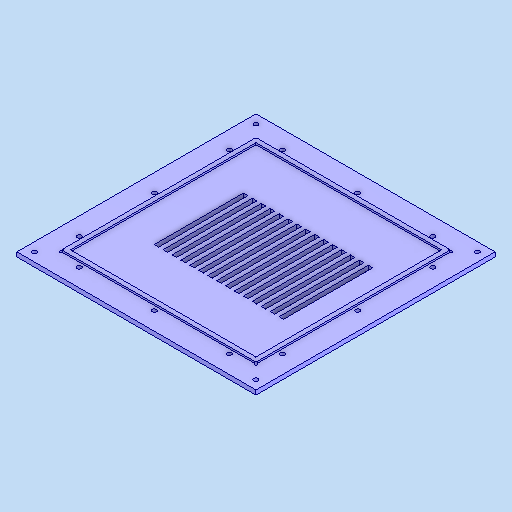
# Autodesk Inventor part: Base_Externa
Saved by Autodesk Inventor 2027 (Build 310192000, 192)
## iProperties
Created: 2026-11-03
Part Number: Base_Externa
Material: Plástico PAEK
Document SubType Name: Modeling
Designer: alex
Density: 1.32 g/cm^3
Appearance: Suave - Blanco
Author: alex
Autodesk Inventor part; units mm, degrees
ref_plane "YZ Plane" through (0, 0, 0) normal (1, 0, 0) x (0, 1, 0)
ref_plane "XZ Plane" through (0, 0, 0) normal (0, 1, 0) x (-1, 0, 0)
ref_plane "XY Plane" through (0, 0, 0) normal (0, 0, 1) x (1, 0, 0)
sketch "Boceto1" plane through (0, 0, 0) normal (0, 1, 0) x (-1, 0, 0)
  arc A0 (-28.3314, 127.2798) -> (-23.3314, 132.2798) centre (-28.3314, 132.2798) ccw
  circle A1 centre (-28.3314, 132.2798) radius 2.5
  line L0 (-33.3314, 127.2798) -> (-28.3314, 127.2798)
  arc A2 (-28.3314, 127.2798) -> (-23.3314, 132.2798) centre (-28.3314, 132.2798) ccw
  line L1 (-23.3314, 137.2798) -> (-23.3314, 132.2798)
  line L2 (-23.3314, 132.2798) -> (-23.3314, 137.2798)
  line L3 (-23.3314, 137.2798) -> (214.6686, 137.2798)
  line L4 (214.6686, 137.2798) -> (214.6686, 132.2798)
  arc A3 (214.6686, 132.2798) -> (219.6686, 127.2798) centre (219.6686, 132.2798) ccw
  line L5 (224.6686, 127.2798) -> (224.6686, -25.7202)
  line L6 (219.6686, 127.2798) -> (224.6686, 127.2798)
  line L7 (224.6686, -115.7202) -> (224.6686, -110.7202)
  line L8 (224.6686, 127.2798) -> (224.6686, -110.7202)
  line L9 (224.6686, -110.7202) -> (219.6686, -110.7202)
  arc A4 (219.6686, -110.7202) -> (214.6686, -115.7202) centre (219.6686, -115.7202) ccw
  line L10 (-23.3314, -120.7202) -> (214.6686, -120.7202)
  line L11 (214.6686, -115.7202) -> (214.6686, -120.7202)
  line L12 (-23.3314, -120.7202) -> (-23.3314, -115.7202)
  line L13 (214.6686, -120.7202) -> (-23.3314, -120.7202)
  line L14 (-23.3314, -120.7202) -> (-23.3314, -115.7202)
  line L15 (-33.3314, -110.7202) -> (-33.3314, 127.2798)
  arc A5 (219.6686, -110.7202) -> (214.6686, -115.7202) centre (219.6686, -115.7202) ccw
  arc A6 (-23.3314, -115.7202) -> (-28.3314, -110.7202) centre (-28.3314, -115.7202) ccw
  arc A7 (-23.3314, -115.7202) -> (-28.3314, -110.7202) centre (-28.3314, -115.7202) ccw
  line L16 (-28.3314, -110.7202) -> (-33.3314, -110.7202)
  line L17 (-28.3314, -110.7202) -> (-33.3314, -110.7202)
  line L18 (95.6686, 137.2798) -> (95.6686, -120.7202)
  line L19 (224.6686, 8.2798) -> (-33.3314, 8.2798)
  circle A8 centre (209.6686, 92.2798) radius 2.5
  circle A9 centre (209.6686, 8.2798) radius 2.5
  circle A10 centre (209.6686, -75.7202) radius 2.5
  circle A11 centre (179.6686, -105.7202) radius 2.5
  circle A12 centre (95.6686, -105.7202) radius 2.5
  circle A13 centre (11.6686, -105.7202) radius 2.5
  circle A14 centre (-18.3314, -75.7202) radius 2.5
  circle A15 centre (-18.3314, 8.2798) radius 2.5
  circle A16 centre (-18.3314, 92.2798) radius 2.5
  circle A17 centre (11.6686, 122.2798) radius 2.5
  circle A18 centre (95.6686, 122.2798) radius 2.5
  circle A19 centre (179.6686, 122.2798) radius 2.5
  line L20 (229.6686, 142.2798) -> (-38.3314, 142.2798)
  line L21 (-38.3314, 142.2798) -> (-38.3314, -125.7202)
  line L22 (-38.3314, -125.7202) -> (229.6686, -125.7202)
  line L23 (229.6686, -125.7202) -> (229.6686, 142.2798)
  circle A20 centre (219.6686, 132.2798) radius 2.5
  circle A21 centre (219.6686, -115.7202) radius 2.5
  circle A22 centre (-28.3314, -115.7202) radius 2.5
  line L24 (204.6686, 117.2798) -> (-13.3314, 117.2798)
  line L25 (-13.3314, 117.2798) -> (-13.3314, -100.7202)
  line L26 (-13.3314, -100.7202) -> (204.6686, -100.7202)
  line L27 (204.6686, -100.7202) -> (204.6686, 117.2798)
  line L28 (-8.3314, 112.2798) -> (199.6686, 112.2798)
  line L29 (199.6686, 112.2798) -> (199.6686, -95.7202)
  line L30 (199.6686, -95.7202) -> (-8.3314, -95.7202)
  line L31 (-8.3314, -95.7202) -> (-8.3314, 112.2798)
  point P0 (0, 0)
  point P1 (-230.3314, 137.2798)
  dimension "d0" = 258
  dimension "d1" = 258
  dimension "d2" = 238
  dimension "d3" = 238
  dimension "d4" = 15
  dimension "d5" = 15
  dimension "d6" = 15
  dimension "d7" = 84
  dimension "d8" = 84
  dimension "d9" = 84
  dimension "d10" = 84
  dimension "d11" = 15
  dimension "d12" = 15
  dimension "d13" = 15
  dimension "d14" = 84
  dimension "d15" = 84
  dimension "d16" = 84
  dimension "d17" = 84
  dimension "d18" = 15
  dimension "d19" = 15
  dimension "d20" = 15
  dimension "d21" = 15
  dimension "d22" = 15
  dimension "d23" = 15
  dimension "d24" = 5
  dimension "d25" = 5
  dimension "d26" = 5
  dimension "d27" = 5
  dimension "d28" = 5
  dimension "d29" = 5
  dimension "d30" = 5
  dimension "d31" = 5
  dimension "d32" = 5
  dimension "d33" = 5
  dimension "d34" = 5
  dimension "d35" = 5
  dimension "d36" = 5
  dimension "d37" = 5
  dimension "d38" = 5
  dimension "d39" = 5
  dimension "d40" = 5
  dimension "d41" = 5
  dimension "d42" = 5
  dimension "d43" = 20
  dimension "d44" = 20
  dimension "d45" = 20
  dimension "d46" = 20
  dimension "d49" = 5
  dimension "d50" = 5
  dimension "d51" = 5
  dimension "d52" = 5
  constraints: 64 end point, 23 centre point, 16 coincident, 14 point on circle, 10 perpendicular, 7 parallel, 4 horizontal, 4 midpoint, 4 point on line, 2 concentric, 1 collinear, 1 vertical
  measures "d0" distance between parallel lines of L15 L8
  measures "d1" distance between parallel lines of L10 L3
  measures "d2" distance of L1.start L3.end
  measures "d3" distance of L15.start L0.start
  measures "d4" distance from line of L3 point (95.669, 122.28)
  measures "d5" distance from line of L3 point (179.669, 122.28)
  measures "d6" distance from line of point (11.669, 122.28) L3
  measures "d7" distance from line of point (179.669, 122.28) L18
  measures "d8" distance from line of L18 point (11.669, 122.28)
  measures "d9" distance from line of point (11.669, -105.72) L18
  measures "d10" distance from line of point (179.669, -105.72) L18
  measures "d11" distance from line of L10 point (95.669, -105.72)
  measures "d12" distance from line of point (179.669, -105.72) L10
  measures "d13" distance from line of point (11.669, -105.72) L10
  measures "d14" distance from line of point (209.669, 92.28) L19
  measures "d15" distance from line of point (209.669, -75.72) L19
  measures "d16" distance from line of point (-18.331, 92.28) L19
  measures "d17" distance from line of point (-18.331, -75.72) L19
  measures "d18" distance from line of L15 point (-18.331, 92.28)
  measures "d19" distance from line of L15 point (-18.331, -75.72)
  measures "d20" distance from line of L15 point (-18.331, 8.28)
  measures "d21" distance from line of point (209.669, 92.28) L8
  measures "d22" distance from line of point (209.669, 8.28) L8
  measures "d23" distance from line of point (209.669, -75.72) L8
  measures "d24" diameter of A8
  measures "d25" diameter of A9
  measures "d26" diameter of A10
  measures "d27" diameter of A11
  measures "d28" diameter of A12
  measures "d29" diameter of A13
  measures "d30" diameter of A14
  measures "d31" diameter of A15
  measures "d32" diameter of A16
  measures "d33" diameter of A17
  measures "d34" diameter of A18
  measures "d35" diameter of A19
  measures "d36" distance between parallel lines of L20 L3
  measures "d37" distance between parallel lines of L21 L15
  measures "d38" distance between parallel lines of L22 L13
  measures "d39" distance between parallel lines of L23 L8
  measures "d40" diameter of A20
  measures "d41" diameter of A21
  measures "d42" diameter of A22
  measures "d43" distance between parallel lines of L27 L5
  measures "d44" distance between parallel lines of L24 L3
  measures "d45" distance between parallel lines of L25 L15
  measures "d46" distance between parallel lines of L26 L13
  measures "d49" distance between parallel lines of L30 L26
  measures "d50" distance between parallel lines of L31 L25
  measures "d51" distance between parallel lines of L28 L24
  measures "d52" distance between parallel lines of L29 L27
extrude "Extrusión1" add sketch "Boceto1" along normal blind 5 contours A0 L1 L3 L18 A18 L24 L25 L19 A15 L15 L0 | L19 A15 L25 L26 L18 A12 L10 L12 A6 L16 L15 | L3 L4 A3 L6 L5 L19 A9 L27 L24 L18 A18 | L25 L24 L18 L28 L31 L19 | L19 L31 L30 L18 L26 L25 | L24 L27 L19 L29 L28 L18 | L31 L28 L18 L19 | L19 L18 L30 L31 | L28 L29 L19 L18 | L18 A12 L26 L27 L19 A9 L5 L8 L9 A4 L11 L10 | L19 L29 L30 L18 | L18 L30 L29 L19 L27 L26 | L23 L22 L21 L20
extrude "Extrusión2" add sketch "Boceto1" along normal blind 7 contours L25 L24 L18 L28 L31 L19 | L19 L31 L30 L18 L26 L25 | L24 L27 L19 L29 L28 L18 | L18 L30 L29 L19 L27 L26
sketch "Boceto2" plane through (0, 0, 0) normal (0, -1, 0) x (1, 0, 0)
  line L0 (-229.6686, 142.2798) -> (38.3314, 142.2798) projected
  line L1 (-229.6686, -125.7202) -> (-229.6686, 142.2798) projected
  line L2 (38.3314, 142.2798) -> (-229.6686, 142.2798)
  line L3 (-229.6686, 142.2798) -> (-229.6686, -125.7202)
  line L4 (-229.6686, -125.7202) -> (38.3314, -125.7202)
  line L5 (38.3314, -125.7202) -> (38.3314, 142.2798)
  line L6 (13.3314, 117.2798) -> (-204.6686, 117.2798) projected
  circle A0 centre (13.3314, 117.2798) radius 10
  line L7 (13.3314, 117.2798) -> (13.3314, -100.7202) projected
  circle A1 centre (13.3314, -100.7202) radius 10
  line L8 (-204.6686, 117.2798) -> (-204.6686, -100.7202) projected
  circle A2 centre (-204.6686, 117.2798) radius 10
  circle A3 centre (-204.6686, -100.7202) radius 10
  circle A4 centre (-204.6686, 117.2798) radius 7.5
  circle A5 centre (13.3314, 117.2798) radius 7.5
  circle A6 centre (13.3314, -100.7202) radius 7.5
  line L9 (-204.6686, -100.7202) -> (13.3314, -100.7202) projected
  circle A7 centre (-204.6686, -100.7202) radius 7.5
  point P0 (0, 0)
  dimension "d55" = 20
  dimension "d56" = 20
  dimension "d57" = 20
  dimension "d58" = 20
  dimension "d59" = 15
  dimension "d60" = 15
  dimension "d61" = 15
  dimension "d62" = 15
  constraints: 8 centre point, 8 end point, 6 coincident, 2 parallel, 1 horizontal, 1 perpendicular
  measures "d55" diameter of A0
  measures "d56" diameter of A1
  measures "d57" diameter of A2
  measures "d58" diameter of A3
  measures "d59" diameter of A4
  measures "d60" diameter of A5
  measures "d61" diameter of A6
  measures "d62" diameter of A7
extrude "Extrusión3" add sketch "Boceto2" along normal blind 5 contours A2 L8 A4 L6 | L6 A4 L8 A2 | A0 L7 A5 L6 | L6 A5 L7 A0 | A3 L9 A7 L8 | L8 A7 L9 A3 | A1 L9 A6 L7 | L7 A6 L9 A1
hole "Agujero1" at (13.3314, 0, 117.2798) at (13.3314, 0, -100.7202) at (-204.6686, 0, -100.7202) at (-204.6686, 0, 117.2798) direction (0, 1, 0) diameter 3 end through all
sketch "Boceto3" plane through (0, 0, 0) normal (0, -1, 0) x (1, 0, 0)
  line L0 (-14.7635, 58.2798) -> (-19.7635, 58.2798)
  line L1 (-19.7635, 58.2798) -> (-19.7635, -41.7202)
  line L2 (-19.7635, -41.7202) -> (-14.7635, -41.7202)
  line L3 (-14.7635, -41.7202) -> (-14.7635, 58.2798)
  line L4 (-229.6686, 142.2798) -> (38.3314, 142.2798) projected
  line L5 (38.3314, -125.7202) -> (-229.6686, -125.7202) projected
  line L6 (-24.7635, 58.2798) -> (-29.7635, 58.2798)
  line L7 (-29.7635, 58.2798) -> (-29.7635, -41.7202)
  line L8 (-29.7635, -41.7202) -> (-24.7635, -41.7202)
  line L9 (-24.7635, -41.7202) -> (-24.7635, 58.2798)
  line L10 (-34.7635, 58.2798) -> (-39.7635, 58.2798)
  line L11 (-39.7635, 58.2798) -> (-39.7635, -41.7202)
  line L12 (-39.7635, -41.7202) -> (-34.7635, -41.7202)
  line L13 (-34.7635, -41.7202) -> (-34.7635, 58.2798)
  line L14 (-44.7635, 58.2798) -> (-49.7635, 58.2798)
  line L15 (-49.7635, 58.2798) -> (-49.7635, -41.7202)
  line L16 (-49.7635, -41.7202) -> (-44.7635, -41.7202)
  line L17 (-44.7635, -41.7202) -> (-44.7635, 58.2798)
  line L18 (-54.7635, 58.2798) -> (-59.7635, 58.2798)
  line L19 (-59.7635, 58.2798) -> (-59.7635, -41.7202)
  line L20 (-59.7635, -41.7202) -> (-54.7635, -41.7202)
  line L21 (-54.7635, -41.7202) -> (-54.7635, 58.2798)
  line L22 (-64.7635, 58.2798) -> (-69.7635, 58.2798)
  line L23 (-69.7635, 58.2798) -> (-69.7635, -41.7202)
  line L24 (-69.7635, -41.7202) -> (-64.7635, -41.7202)
  line L25 (-64.7635, -41.7202) -> (-64.7635, 58.2798)
  line L26 (-74.7635, 58.2798) -> (-79.7635, 58.2798)
  line L27 (-79.7635, 58.2798) -> (-79.7635, -41.7202)
  line L28 (-79.7635, -41.7202) -> (-74.7635, -41.7202)
  line L29 (-74.7635, -41.7202) -> (-74.7635, 58.2798)
  line L30 (-84.7635, 58.2798) -> (-89.7635, 58.2798)
  line L31 (-89.7635, 58.2798) -> (-89.7635, -41.7202)
  line L32 (-89.7635, -41.7202) -> (-84.7635, -41.7202)
  line L33 (-84.7635, -41.7202) -> (-84.7635, 58.2798)
  line L34 (-94.7635, 58.2798) -> (-99.7635, 58.2798)
  line L35 (-99.7635, 58.2798) -> (-99.7635, -41.7202)
  line L36 (-99.7635, -41.7202) -> (-94.7635, -41.7202)
  line L37 (-94.7635, -41.7202) -> (-94.7635, 58.2798)
  line L38 (-104.7635, 58.2798) -> (-109.7635, 58.2798)
  line L39 (-109.7635, 58.2798) -> (-109.7635, -41.7202)
  line L40 (-109.7635, -41.7202) -> (-104.7635, -41.7202)
  line L41 (-104.7635, -41.7202) -> (-104.7635, 58.2798)
  line L42 (-114.7635, 58.2798) -> (-119.7635, 58.2798)
  line L43 (-119.7635, 58.2798) -> (-119.7635, -41.7202)
  line L44 (-119.7635, -41.7202) -> (-114.7635, -41.7202)
  line L45 (-114.7635, -41.7202) -> (-114.7635, 58.2798)
  line L46 (-124.7635, 58.2798) -> (-129.7635, 58.2798)
  line L47 (-129.7635, 58.2798) -> (-129.7635, -41.7202)
  line L48 (-129.7635, -41.7202) -> (-124.7635, -41.7202)
  line L49 (-124.7635, -41.7202) -> (-124.7635, 58.2798)
  line L50 (-134.7635, 58.2798) -> (-139.7635, 58.2798)
  line L51 (-139.7635, 58.2798) -> (-139.7635, -41.7202)
  line L52 (-139.7635, -41.7202) -> (-134.7635, -41.7202)
  line L53 (-134.7635, -41.7202) -> (-134.7635, 58.2798)
  line L54 (-144.7635, 58.2798) -> (-149.7635, 58.2798)
  line L55 (-149.7635, 58.2798) -> (-149.7635, -41.7202)
  line L56 (-149.7635, -41.7202) -> (-144.7635, -41.7202)
  line L57 (-144.7635, -41.7202) -> (-144.7635, 58.2798)
  line L58 (-154.7635, 58.2798) -> (-159.7635, 58.2798)
  line L59 (-159.7635, 58.2798) -> (-159.7635, -41.7202)
  line L60 (-159.7635, -41.7202) -> (-154.7635, -41.7202)
  line L61 (-154.7635, -41.7202) -> (-154.7635, 58.2798)
  point P0 (0, 0)
  dimension "d72" = 5
  dimension "d73" = 100
  dimension "d74" = 84
  dimension "d75" = 84
  dimension "d78" = 10
  constraints: 120 end point, 2 horizontal, 2 parallel, 1 collinear, 1 perpendicular, 111 other
  measures "d72" distance of L2.end L1.end
  measures "d73" distance of L1.end L0.end
  measures "d74" distance between parallel lines of L4 L0
  measures "d75" distance between parallel lines of L5 L2
  measures "d78" distance of L0.start L6.start
extrude "Extrusión4" cut sketch "Boceto3" against normal blind 5
